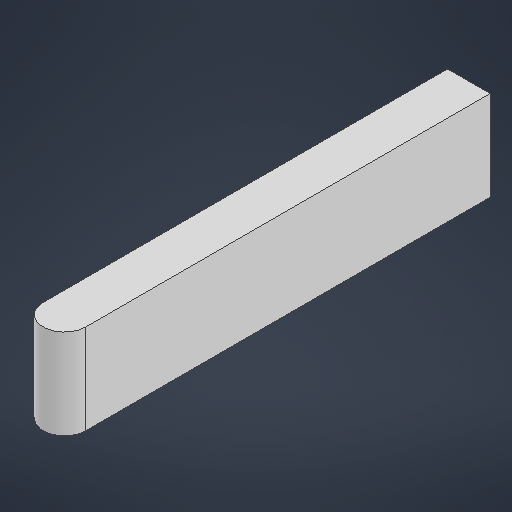
# Autodesk Inventor part: Shaft Key
Saved by Autodesk Inventor 2026.2 (Build 302298010, 298A)
## iProperties
Created: 2026-08-20
Part Number: Shaft Key
Material: Generic
Document SubType Name: Modeling
Designer: User
Density: 1 g/cm^3
Appearance: Default
Author: User
Autodesk Inventor part; units mm, degrees
ref_plane "YZ Plane" through (0, 0, 0) normal (1, 0, 0) x (0, 1, 0)
ref_plane "XZ Plane" through (0, 0, 0) normal (0, 1, 0) x (-1, 0, 0)
ref_plane "XY Plane" through (0, 0, 0) normal (0, 0, 1) x (1, 0, 0)
sketch "Sketch2" plane through (0, 0, 0) normal (0, 1, 0) x (-1, 0, 0)
  line L0 (-0.9, 9) -> (0.9, 9)
  line L1 (0.9, 9) -> (0.9, -9)
  line L2 (0.9, -9) -> (-0.9, -9)
  line L3 (-0.9, -9) -> (-0.9, 9)
  line L4 (-0.9, 9) -> (0.9, -9) construction
  line L5 (0.9, 9) -> (-0.9, -9) construction
  point P0 (0, 0)
  dimension "d0" = 1.8
  dimension "d1" = 18
  constraints: 12 end point, 2 midpoint, 2 parallel, 1 horizontal, 1 perpendicular
  measures "d0" distance of L1.end L2.end
  measures "d1" distance of L0.end L1.end
extrude "Extrusion1" add sketch "Sketch2" along normal blind 3.8
fillet "Fillet2" radius 0.9 2 edges at (0.9, 1.9, 9) (-0.9, 1.9, 9)
body "Solid1"
